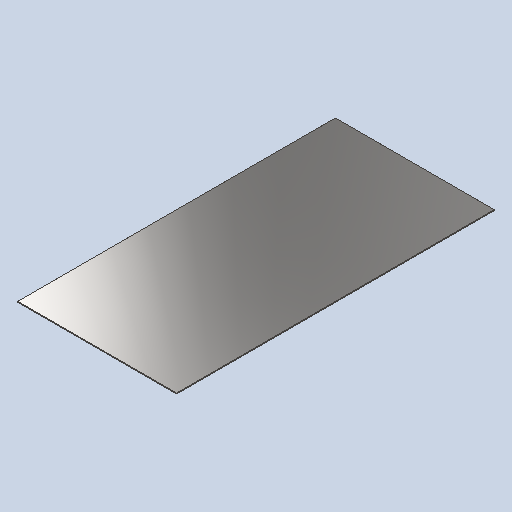
# Autodesk Inventor part: RDS-3001 Deck 750x1500
Saved by Autodesk Inventor 2026.2 (Build 302298000, 298)
## iProperties
Created: 2026-10-12
Part Number: RDS-3001 Deck 750x1500
Material: Stainless Steel, Austenitic
Description: Deck plate 750x1500 t4
Document SubType Name: Modeling
Designer: admin
Stock Number: Настил 750х1500х4 AISI 304 (рифлёный лист)
Density: 8 g/cm^3
Appearance: Semi-Polished
Author: admin
Autodesk Inventor part; units mm, degrees
ref_plane "YZ Plane" through (0, 0, 0) normal (1, 0, 0) x (0, 1, 0)
ref_plane "XZ Plane" through (0, 0, 0) normal (0, 1, 0) x (-1, 0, 0)
ref_plane "XY Plane" through (0, 0, 0) normal (0, 0, 1) x (1, 0, 0)
sketch "Sketch1" plane through (0, 0, 0) normal (0, 1, 0) x (-1, 0, 0)
  line L0 (375, -750) -> (-375, -750)
  line L1 (-375, -750) -> (-375, 750)
  line L2 (-375, 750) -> (375, 750)
  line L3 (375, 750) -> (375, -750)
  constraints: 8 end point, 2 parallel, 1 horizontal, 1 perpendicular
extrude "Extrusion1" add sketch "Sketch1" along normal blind 4
equation "\"d0\" = Deck3001_Thickness"
equation "\"Deck3001_Thickness\" = 4"
body "Solid1"
